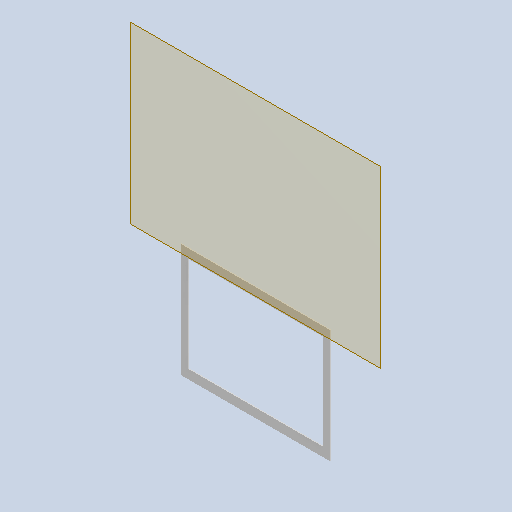
# Autodesk Inventor part: зона для листа
Saved by Autodesk Inventor 2024.2 (Build 282272000, 272)
## iProperties
Created: 2026-10-08
Part Number: зона для листа
Material: Типовые
Document SubType Name: Modeling
Designer: User
Density: 1 g/cm^3
Appearance: По умолчанию
Author: User
Autodesk Inventor part; units mm, degrees
ref_plane "YZ Plane" through (0, 0, 0) normal (1, 0, 0) x (0, 1, 0)
ref_plane "XZ Plane" through (0, 0, 0) normal (0, 1, 0) x (-1, 0, 0)
ref_plane "XY Plane" through (0, 0, 0) normal (0, 0, 1) x (1, 0, 0)
ref_plane "РабПлоскость1" through (210, 300, 0) normal (0, 0, 1) x (1, 0, 0)
sketch "Эскиз1" plane through (210, 300, 0) normal (0, 0, 1) x (1, 0, 0)
  line L0 (-250, -175) -> (250, -175) projected
  line L1 (-250, -175) -> (250, -175)
  line L2 (250, -175) -> (250, -425)
  line L3 (250, -425) -> (-250, -425)
  line L4 (-250, -425) -> (-250, -175)
  line L5 (250, -425) -> (250, -175) projected
  line L6 (165, -175) -> (165, -425)
  line L7 (-165, -175) -> (-165, -425)
  line L8 (-148.5, -195) -> (148.5, -195)
  line L9 (148.5, -195) -> (148.5, -405)
  line L10 (148.5, -405) -> (-148.5, -405)
  line L11 (-148.5, -405) -> (-148.5, -195)
  point P0 (-210, -300)
  dimension "d0" = 0
  dimension "d1" = 0
  dimension "d2" = 85
  dimension "d3" = 85
  dimension "d4" = 210
  dimension "d5" = 297
  dimension "d6" = 16.5
  dimension "d7" = 20
  constraints: 20 end point, 4 parallel, 4 perpendicular, 4 point on line, 2 horizontal
  measures "d0" distance between parallel lines of L5 L2
  measures "d1" distance from line of L5.start L3
  measures "d2" distance between parallel lines of L2 L6
  measures "d3" distance between parallel lines of L4 L7
  measures "d4" distance of L8.end L9.end
  measures "d5" distance of L9.end L10.end
  measures "d6" distance between parallel lines of L9 L6
  measures "d7" distance between parallel lines of L10 L3
extrude "Выдавливание1" add sketch "Эскиз1" against normal blind 2 contours L0 L6 L3 L7
